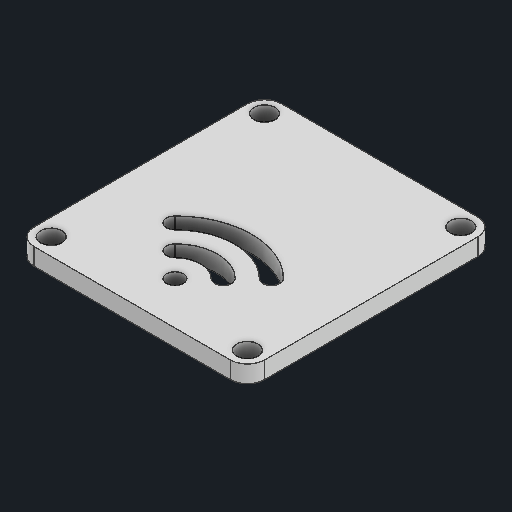
# Autodesk Inventor part: c3 cover
Saved by Autodesk Inventor 2027 (Build 310192000, 192)
## iProperties
Created: 2026-09-27
Part Number: c3 cover
Material: 일반
Document SubType Name: Modeling
Designer: work
Density: 1 g/cm^3
Appearance: 기본값
Author: work
Autodesk Inventor part; units mm, degrees
ref_plane "YZ Plane" through (0, 0, 0) normal (1, 0, 0) x (0, 1, 0)
ref_plane "XZ Plane" through (0, 0, 0) normal (0, 1, 0) x (-1, 0, 0)
ref_plane "XY Plane" through (0, 0, 0) normal (0, 0, 1) x (1, 0, 0)
sketch "스케치1" plane through (0, 0, 0) normal (0, 1, 0) x (-1, 0, 0)
  line L0 (0, 0) -> (19, 0)
  line L1 (19, 0) -> (19, -25)
  line L2 (19, -25) -> (0, -25)
  line L3 (0, -25) -> (0, 0)
  line L4 (14.5, -25) -> (4.5, -25)
  line L5 (4.5, -25) -> (4.5, -27)
  line L6 (4.5, -27) -> (14.5, -27)
  line L7 (14.5, -27) -> (14.5, -25)
  line L8 (21, -27) -> (21, 2)
  line L9 (21, 2) -> (-2, 2)
  line L10 (-2, 2) -> (-2, -27)
  line L11 (-2, -27) -> (21, -27)
  line L12 (18, -24) -> (18, -1)
  line L13 (18, -1) -> (1, -1)
  line L14 (1, -1) -> (1, -24)
  line L15 (1, -24) -> (18, -24)
  line L16 (18, -1) -> (17, -1)
  line L17 (17, -1) -> (17, -12.5)
  line L18 (17, -12.5) -> (18, -12.5)
  line L19 (18, -12.5) -> (18, -1)
  line L20 (9.5, -1) -> (9.5, -24) construction
  line L21 (2, -1) -> (2, -12.5)
  line L22 (2, -12.5) -> (1, -12.5)
  line L23 (17, -1) -> (15, -1)
  line L24 (15, -1) -> (15, -2)
  line L25 (15, -2) -> (17, -2)
  line L26 (17, -2) -> (17, -1)
  line L27 (4, -1) -> (4, -2)
  line L28 (4, -2) -> (2, -2)
  point P0 (19, -12.5)
  point P1 (14.5, -26)
  point P2 (9.5, -27)
  dimension "d0" = 19
  dimension "d1" = 25
  dimension "d2" = 2
  dimension "d3" = 10
  dimension "d4" = 1
  dimension "d5" = 1
  dimension "d6" = 11.5
  dimension "d7" = 1
  dimension "d8" = 2
  constraints: 58 end point, 12 parallel, 6 midpoint, 6 perpendicular, 6 symmetric about line, 4 horizontal, 1 point on line, 6 other
  measures "d0" distance of L1.end L2.end
  measures "d1" distance of L0.end L1.end
  measures "d2" distance from line of point (19, -12.5) L8
  measures "d3" distance from line of L5 point (14.5, -26)
  measures "d4" distance between parallel lines of L1 L12
  measures "d5" distance of L17.end L18.end
  measures "d6" distance of L16.end L17.end
  measures "d7" distance of L23.end L24.end
  measures "d8" distance of L24.end L25.end
extrude "돌출1" add sketch "스케치1" along normal blind 2 contours L3 L2 L5 L11 L10 L9 L8 L7 L1 L0 | L0 L1 L2 L3 | L2 L7 L6 L5 | L15 L14 L22 L21 L28 L27 L13 L24 L25 L17 L18 L12 | L18 L17 L13 L12 | L14 L13 L21 L22 | L17 L25 L24 L13 | L13 L27 L28 L21
extrude "돌출2" add sketch "스케치1" against normal blind 2.9 contours L18 L17 L13 L12 | L14 L13 L21 L22 | L17 L25 L24 L13 | L13 L27 L28 L21
fillet "모깎기1" radius 0.5 8 edges at (-17, -1.45, -2) (-18, -1.45, -1) (-15, -1.45, -2) (-17, -1.45, -12.5) (-2, -1.45, -12.5) (-2, -1.45, -2) (-4, -1.45, -2) (-1, -1.45, -1)
fillet "모깎기2" radius 1.2 14 edges at (-17.1464, 0, -12.3536) (-17, 0, -7.25) (-16.8536, 0, -2.1464) (-16, 0, -2) (-15.1464, 0, -1.8536) (-15, 0, -1.25) (-17.75, 0, -12.5) (-1.8536, 0, -12.3536) (-2, 0, -7.25) (-2.1464, 0, -2.1464) (-3, 0, -2) (-3.8536, 0, -1.8536) (-4, 0, -1.25) (-1.25, 0, -12.5)
sketch "스케치2" plane through (0, 0, 0) normal (0, -1, 0) x (1, 0, 0)
  circle A0 centre (-9.5, -3) radius 1
  line L0 (-21, 2) -> (2, 2) projected
  arc A1 (-12.3284, -5.8284) -> (-6.6716, -5.8284) centre (-9.5, -3) ccw construction
  arc A2 (-13.0355, -6.5355) -> (-5.9645, -6.5355) centre (-9.5, -3) ccw
  arc A3 (-11.6213, -5.1213) -> (-7.3787, -5.1213) centre (-9.5, -3) ccw
  arc A4 (-11.6213, -5.1213) -> (-13.0355, -6.5355) centre (-12.3284, -5.8284) ccw
  arc A5 (-5.9645, -6.5355) -> (-7.3787, -5.1213) centre (-6.6716, -5.8284) ccw
  line L1 (-9.5, -3) -> (-12.3284, -5.8284) construction
  line L2 (-9.5, -3) -> (-6.6716, -5.8284) construction
  arc A6 (-15.1569, -8.6569) -> (-3.8431, -8.6569) centre (-9.5, -3) ccw construction
  arc A7 (-15.864, -9.364) -> (-3.136, -9.364) centre (-9.5, -3) ccw
  arc A8 (-14.4497, -7.9497) -> (-4.5503, -7.9497) centre (-9.5, -3) ccw
  arc A9 (-14.4497, -7.9497) -> (-15.864, -9.364) centre (-15.1569, -8.6569) ccw
  arc A10 (-3.136, -9.364) -> (-4.5503, -7.9497) centre (-3.8431, -8.6569) ccw
  point P0 (0, 0)
  point P1 (-9.5, 2)
  point P2 (-9.5, 2)
  dimension "d15" = 2
  dimension "d16" = 5
  dimension "d17" = 90
  dimension "d18" = 2
  dimension "d19" = 45
  dimension "d20" = 4
  dimension "d21" = 2
  dimension "d22" = 2
  constraints: 20 point on circle, 11 centre point, 8 tangent, 4 end point, 2 midpoint, 2 point on line, 1 coincident, 1 concentric, 1 vertical alignment
  measures "d15" diameter of A0
  measures "d16" distance of point (-9.5, 2) A0.centre
  measures "d17" angle of L1 L2
  measures "d18" diameter of A4
  measures "d19" angle of L0 L2
  measures "d20" radius of A1
  measures "d21" radial gap between concentric circles of A8 A7
  measures "d22" radial gap between concentric circles of A2 A8
extrude "돌출3" cut sketch "스케치2" against normal through all
sketch "스케치3" plane through (0, 0, 0) normal (0, -1, 0) x (1, 0, 0)
  line L0 (-21, -27) -> (-21, 2) projected
  circle A0 centre (-21, 0) radius 1.25
  line L1 (-21, 2) -> (2, 2) projected
  line L2 (-9.5, 2) -> (-9.5, -27) construction
  line L3 (2, -27) -> (-21, -27) projected
  circle A1 centre (-21, -25) radius 1.25
  line L4 (-21, -25) -> (-21, 0) construction
  line L5 (-19, -25) -> (-19, 0)
  line L6 (-23, 0) -> (-23, -25)
  arc A2 (-23, -25) -> (-19, -25) centre (-21, -25) ccw
  arc A3 (-19, 0) -> (-23, 0) centre (-21, 0) ccw
  line L7 (2, -27) -> (2, 2)
  circle A4 centre (2, 0) radius 1.25
  line L8 (2, 2) -> (-21, 2)
  line L9 (-21, -27) -> (2, -27)
  circle A5 centre (2, -25) radius 1.25
  line L10 (2, -25) -> (2, 0) construction
  line L11 (0, -25) -> (0, 0)
  line L12 (4, 0) -> (4, -25)
  arc A6 (0, -25) -> (4, -25) centre (2, -25) ccw
  arc A7 (4, 0) -> (0, 0) centre (2, 0) ccw
  point P0 (0, 0)
  point P1 (-21, -12.5)
  point P2 (2, -12.5)
  point P3 (-21, -26.25)
  point P4 (-21, -23.75)
  point P5 (-21, -1.25)
  point P6 (-21, 1.25)
  point P7 (2, 1.25)
  point P8 (2, -1.25)
  point P9 (2, -23.75)
  point P10 (2, -26.25)
  dimension "d25" = 2.5
  dimension "d26" = 2.5
  dimension "d27" = 2
  dimension "d28" = 2
  constraints: 24 end point, 11 symmetric about line, 9 point on circle, 8 centre point, 4 point on line, 4 tangent, 3 midpoint, 1 collinear, 1 parallel, 4 other
  measures "d25" diameter of A0
  measures "d26" diameter of A1
  measures "d27" distance of L0.start L4.start
  measures "d28" distance of L0.end L4.end
extrude "돌출4" add sketch "스케치3" against normal up to surface (2 mm away) contours A2 L6 A3 L0 A0 A1 | L7 A5 A4 A7 L12 A6
extrude "돌출5" cut sketch "스케치3" against normal through all contours L0 A1 | A5 L7 | L0 A0 | A4 L7 picked at (-20.3127, -24.7402) picked at (1.1991, -25.0502) picked at (-20.0742, -0.0927) picked at (1.5864, 0.0502)
